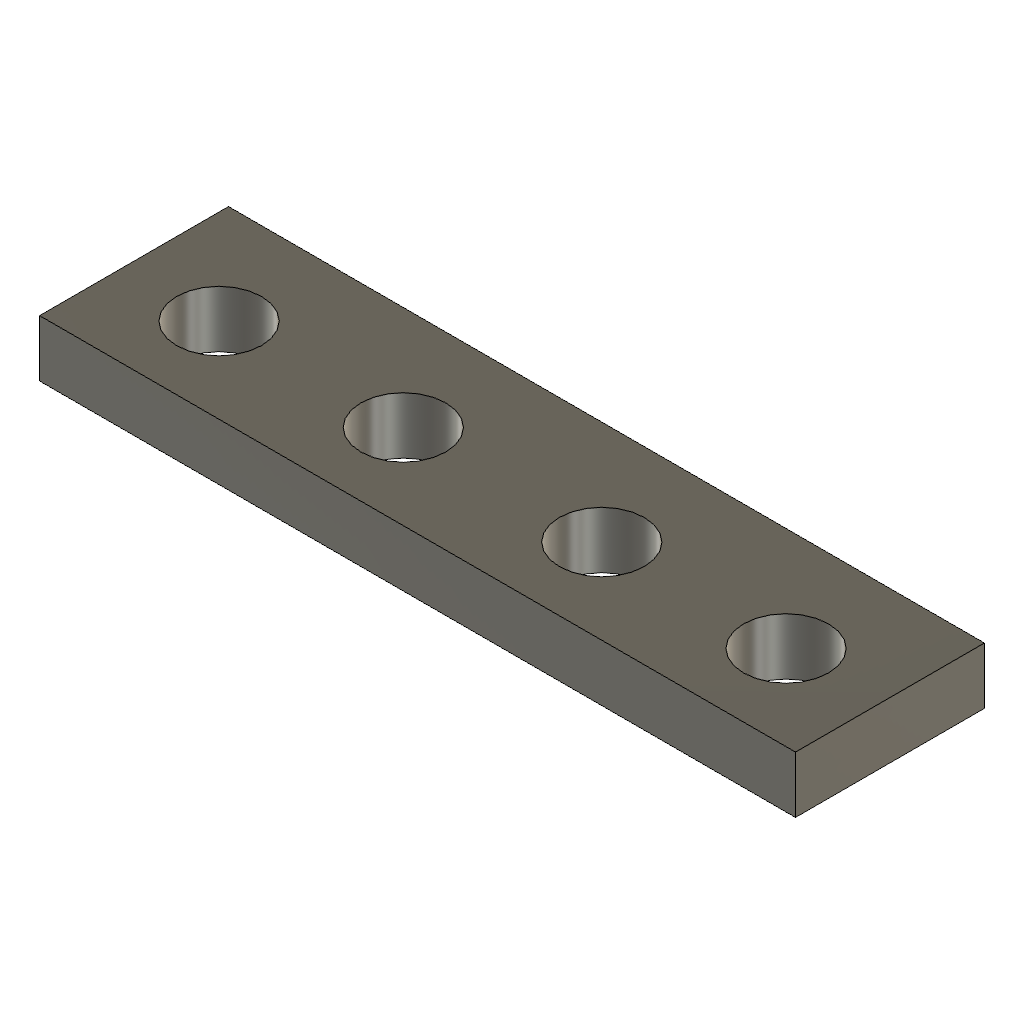
Servo to cover connector (Autodesk Fusion 360 design; units mm, degrees)
Autodesk Fusion 360 part; units mm, degrees
sketch "Sketch1" plane through (0, 0, 0) normal (0, 0, 1) x (1, 0, 0)
  line L0 (20, 5) -> (-20, 5)
  line L1 (-20, 5) -> (-20, -5)
  line L2 (-20, -5) -> (20, -5)
  line L3 (20, -5) -> (20, 5)
  line L4 (20, 5) -> (-20, -5) construction
  line L5 (-20, 5) -> (20, -5) construction
  circle A0 centre (-15, -0.5) radius 2.25
  circle A1 centre (15, -0.5) radius 2.25
  line L6 (-10, 5) -> (10, 5)
  line L7 (10, 5) -> (10, -5)
  line L8 (10, -5) -> (-10, -5)
  line L9 (-10, -5) -> (-10, 5)
  circle A2 centre (-5.25, -0.5) radius 2.25
  circle A3 centre (5.25, -0.5) radius 2.25
  dimension "d1" = 40
  dimension "d2" = 10
  dimension "d3" = 4.5
  dimension "d4" = 4.5
  dimension "d7" = 4.5
  dimension "d8" = 4.5
  dimension "d9" = 5
  dimension "d10" = 5
  dimension "d11" = 20
  dimension "d12" = 10
  dimension "d13" = 4.5
  dimension "d14" = 4.5
  dimension "d15" = 4.75
  dimension "d16" = 4.75
  constraint horizontal L0
  constraint perpendicular L0 L1
  constraint parallel L0 L2
  constraint parallel L1 L3
  constraint coincident L4 origin
  constraint coincident L5 origin
  constraint horizontal L6
  constraint vertical L7
  constraint horizontal L8
  constraint vertical L9
  constraint coincident L0 L6.start
  measures "d1" distance of L1.end L2.end
  measures "d2" distance of L0.end L1.end
  measures "d3" diameter of A0
  measures "d4" diameter of A1
  measures "d7" distance of L2 A0.centre
  measures "d8" distance of L2 A1.centre
  measures "d9" distance of L1 A0.centre
  measures "d10" distance of L3 A1.centre
  measures "d11" distance of L6.start L6.end
  measures "d12" distance of L3 L7
  measures "d13" diameter of A2
  measures "d14" diameter of A3
  measures "d15" distance of L9 A2.centre
  measures "d16" distance of L7 A3.centre
extrude "Extrude1" add sketch "Sketch1" along normal blind 3
